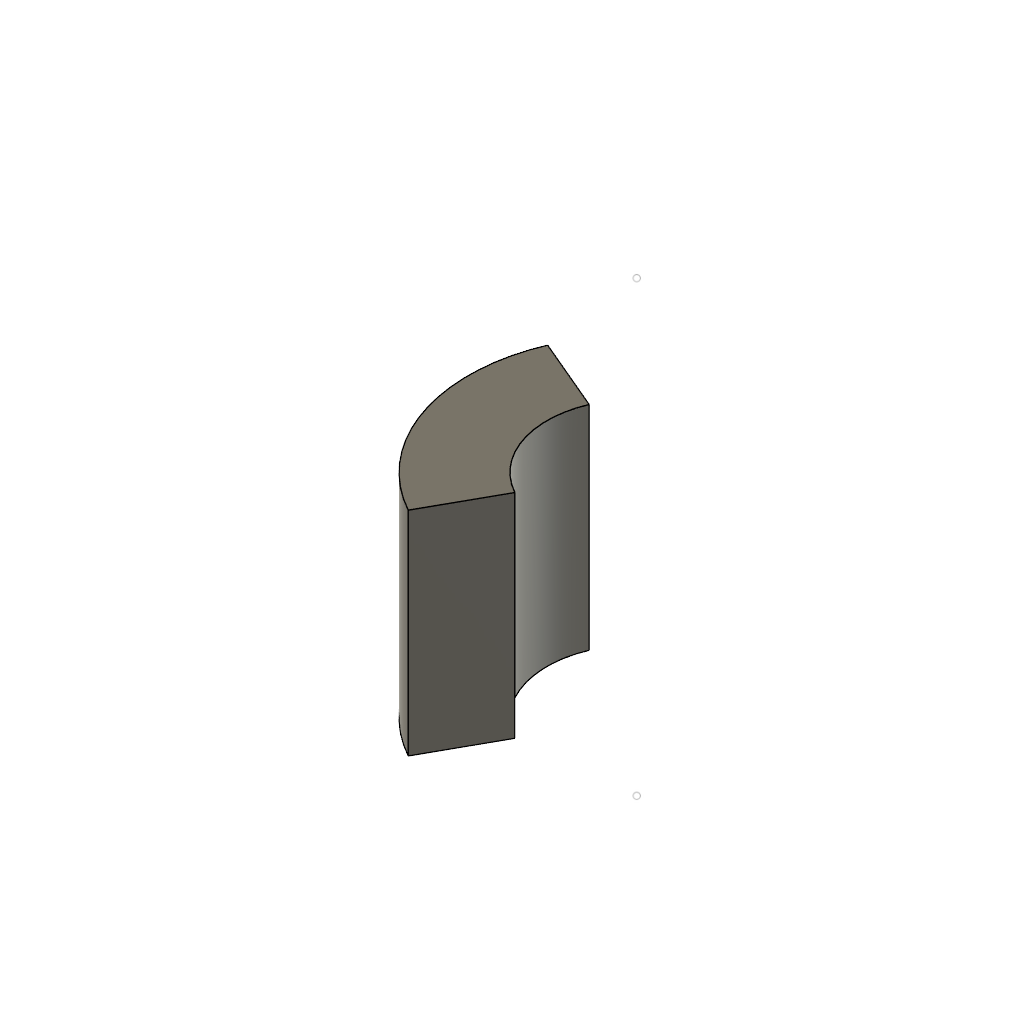
origin (Autodesk Fusion 360 design; units mm, degrees)
part number: 2026-11-27-16-03-30-666
Autodesk Fusion 360 part; units mm, degrees
sketch "AxisSupport" plane through (0, 0, 0) normal (0, 0, 1) x (1, 0, 0)
  point P0 (-17, 23)
  point P1 (-17, 63)
sketch "RevolveProfile" plane through (0, 0, 0) normal (0, 0, 1) x (1, 0, 0)
  line L0 (-25, 29) -> (-25, 48)
  line L1 (-25, 48) -> (-32, 48)
  line L2 (-32, 48) -> (-32, 29)
  line L3 (-32, 29) -> (-25, 29)
revolve "UnequalRevolve" add sketch "RevolveProfile" angle 61 about axis through (-17, 15, 0) along (0, 1, 0) second angle 23
